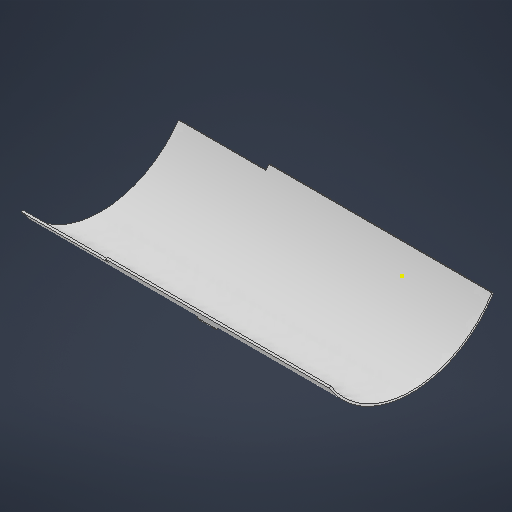
# Autodesk Inventor part: 22.10.2025-06
Saved by Autodesk Inventor 2026.1 (Build 301233020, 233B)
## iProperties
Created: 2025-12-14
Part Number: 22.10.2025-06
Material: Ogólny
Document SubType Name: Modeling
Designer: Nitro
Density: 1 g/cm^3
Appearance: Domyślna
Author: Nitro
Autodesk Inventor part; units mm, degrees
ref_plane "XZ Plane" through (0, 0, 0) normal (0, 1, 0) x (-1, 0, 0)
ref_plane "XY Plane" through (0, 0, 0) normal (0, 0, 1) x (1, 0, 0)
sketch "Szkic1" plane through (0, 0, 0) normal (1, 0, 0) x (0, 1, 0)
  circle A0 centre (0, 0) radius 50
  line L0 (0, 0) -> (-26.496, 42.4024)
  line L1 (0, 0) -> (50, 0) construction
  line L2 (0, 0) -> (-26.496, -42.4024)
  line L3 (0, 0) -> (50, 0) construction
  circle A1 centre (0, 0) radius 49
  point P0 (-25.966, -41.5544)
  point P1 (-25.966, 41.5544)
  dimension "d0" = 100
  dimension "d1" = 122
  dimension "d2" = 122
  dimension "d3" = 98
  constraints: 8 end point, 2 centre point, 2 coincident, 2 equal length, 2 horizontal, 2 point on circle
  measures "d0" diameter of A0
  measures "d1" angle of L1 L0
  measures "d2" angle of L2 L3
  measures "d3" diameter of A1
sketch "Szkic2" plane through (0, 0, 0) normal (1, 0, 0) x (0, 1, 0)
  circle A0 centre (0, 0) radius 49 projected
  line L0 (0, 0) -> (-24.5, 42.4352)
  line L1 (0, 0) -> (49, 0) construction
  line L2 (0, 0) -> (-24.5, -42.4352)
  line L3 (0, 0) -> (49, 0) construction
  line L4 (0, 0) -> (-28.1052, -40.1385)
  line L5 (0, 0) -> (49, 0) construction
  line L6 (0, 0) -> (-28.2126, 40.2918)
  line L7 (0, 0) -> (49.1872, 0) construction
  line L8 (-28.1052, -40.1385) -> (-27.5317, -39.3193)
  line L9 (-27.5317, -39.3193) -> (-24.0917, -41.728)
  line L10 (-28.1052, 40.1385) -> (-27.5317, 39.3193)
  line L11 (-27.5317, 39.3193) -> (-23.9087, 41.411)
  line L12 (0, 0) -> (-26.496, 42.4024) projected
  line L13 (-28.1052, 40.1385) -> (-29.1517, 41.6329)
  line L14 (-28.1052, -40.1385) -> (-28.6788, -40.9576)
  circle A1 centre (0, 0) radius 50 projected
  point P0 (-28.6788, 40.9576)
  dimension "d4" = 120
  dimension "d5" = 120
  dimension "d6" = 125
  dimension "d7" = 125
  dimension "d8" = 1
  dimension "d9" = 1
  constraints: 28 end point, 6 point on line, 5 point on circle, 4 equal length, 4 horizontal, 2 perpendicular
  measures "d4" angle of L1 L0
  measures "d5" angle of L2 L3
  measures "d6" angle of L4 L5
  measures "d7" angle of L7 L6
  measures "d8" distance of L4.end L8.end
  measures "d9" distance of L10.start L10.end
extrude "Wyciągnięcie proste2" add sketch "Szkic1" along normal blind 150 contours L0 A1 L2 A0 picked at (-31.1458, 38.4466)
extrude "Wyciągnięcie proste3" cut sketch "Szkic2" along normal blind 5 contours A0 L12 A1 L14 | A0 L6 L13 A1 L12
sketch "Szkic4" plane through (150, 0, 0) normal (1, 0, 0) x (0, 0, -1)
  point P0 (0, 0)
sketch "Szkic5" plane through (150, 0, 0) normal (1, 0, 0) x (0, 0, -1)
  point P0 (0, 0)
sketch "Szkic6" plane through (5, 0, 0) normal (-1, 0, 0) x (0, 0, 1)
  line L0 (-42.4024, -26.496) -> (-41.5544, -25.966) projected
  arc A0 (-42.4024, -26.496) -> (-40.9576, -28.6788) centre (0, 0) ccw projected
  line L1 (-40.1385, -28.1052) -> (-40.9576, -28.6788) projected
  arc A1 (-41.5544, -25.966) -> (-40.1385, -28.1052) centre (0, 0) ccw projected
  line L2 (41.5544, -25.966) -> (42.4024, -26.496) projected
  arc A2 (40.1385, -28.1052) -> (41.5544, -25.966) centre (0, 0) ccw projected
  line L3 (40.9576, -28.6788) -> (40.1385, -28.1052) projected
  arc A3 (40.9576, -28.6788) -> (42.4024, -26.496) centre (0, 0) ccw projected
extrude "Wyciągnięcie proste4" cut sketch "Szkic6" against normal blind 35
sketch "Szkic7" plane through (0, 0, 0) normal (-1, 0, 0) x (0, 0, 1)
  line L0 (-40.1385, -28.1052) -> (-40.9576, -28.6788) projected
  arc A0 (-40.9576, -28.6788) -> (40.9576, -28.6788) centre (0, 0) ccw projected
  line L1 (40.9576, -28.6788) -> (40.1385, -28.1052) projected
  arc A1 (-40.1385, -28.1052) -> (40.1385, -28.1052) centre (0, 0) ccw projected
extrude "Wyciągnięcie proste5" add sketch "Szkic7" along normal blind 5
sketch "Szkic8" plane through (150, 0, 0) normal (1, 0, 0) x (0, 0, -1)
  line L0 (-41.5544, -25.966) -> (-42.4024, -26.496) projected
  arc A0 (-42.4024, -26.496) -> (42.4024, -26.496) centre (0, 0) ccw projected
  line L1 (42.4024, -26.496) -> (41.5544, -25.966) projected
  arc A1 (-41.5544, -25.966) -> (41.5544, -25.966) centre (0, 0) ccw projected
extrude "Wyciągnięcie proste6" add sketch "Szkic8" along normal blind 5
ref_plane "Płaszczyzna konstrukcyjna1" through (60, 0, 0) normal (1, 0, 0) x (0, 1, 0)
sketch "Szkic9" plane through (60, 0, 0) normal (1, 0, 0) x (0, 1, 0)
  arc A0 (-28.6788, 40.9576) -> (-28.6788, -40.9576) centre (0, 0) ccw projected
  arc A1 (-28.1052, 40.1385) -> (-28.1052, -40.1385) centre (0, 0) ccw projected
  line L0 (-50, 15) -> (-50, -15)
  line L1 (-42.5, -15) -> (-57.5, -15)
  line L2 (-42.5, 15) -> (-57.5, 15)
  line L3 (-57.5, 15) -> (-57.5, -15)
  line L4 (-42.5, 15) -> (-42.5, -15)
  point P0 (-50, 0)
  point P1 (-47.697, 15)
  point P2 (-47.697, -15)
  dimension "d23" = 30
  dimension "d24" = 15
  dimension "d25" = 15
  constraints: 10 end point, 3 midpoint, 2 parallel, 1 horizontal, 1 perpendicular, 1 point on circle, 1 vertical
  measures "d23" distance of L0.start L0.end
  measures "d24" distance of L1.start L1.end
  measures "d25" distance of L2.start L2.end
extrude "Wyciągnięcie proste7" add sketch "Szkic9" along normal blind 10 contours A0 L0 L2 | L0 L1 L3 L2 | A0 L1 L0
sketch "Szkic10" plane through (70, 0, 0) normal (1, 0, 0) x (0, 0, -1)
  circle A0 centre (0, -71.211) radius 20.2741
  point P0 (0, 0)
  point P1 (-15, -57.5)
  point P2 (15, -57.5)
  constraints: 1 centre point
extrude "Wyciągnięcie proste8" cut sketch "Szkic10" against normal blind 3
sketch "Szkic11" plane through (60, 0, 0) normal (-1, 0, 0) x (0, 0, 1)
  arc A0 (14.9348, -57.5) -> (-14.9348, -57.5) centre (0, -71.211) ccw projected
  circle A1 centre (0, -71.211) radius 20.2741
  point P0 (0, 0)
  point P1 (-14.9348, -57.5)
  point P2 (14.9348, -57.5)
  constraints: 1 centre point, 1 coincident, 1 concentric
extrude "Wyciągnięcie proste9" cut sketch "Szkic11" against normal blind 3
fillet "Zaokrąglenie1" radius 1 2 edges at (63, -57.5, 0) (67, -57.5, 0)
fillet "Zaokrąglenie2" radius 1 4 edges at (60, -50.9369, 0) (70, -50.9369, 0) (65, -57.5, -15) (65, -57.5, 15)
